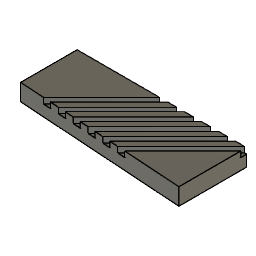
strip_cut (Autodesk Fusion 360 design; units mm, degrees)
Autodesk Fusion 360 part; units mm, degrees
sketch "Sketch1" plane through (0, 0, 0) normal (0, 0, 1) x (1, 0, 0)
  line L0 (0, 0) -> (30, -2)
  line L1 (30, -2) -> (30, 10)
  line L2 (30, 10) -> (0, 10)
  line L3 (0, 10) -> (0, 0)
extrude "Extrude1" add sketch "Sketch1" along normal blind 3
sketch "Sketch2" plane through (0, 0, 3) normal (0, 0, 1) x (1, 0, 0)
  line L0 (0, 10) -> (0, 0)
  line L1 (0, 0) -> (30, -2)
  line L2 (30, -2) -> (30, 10)
  line L3 (30, 10) -> (0, 10)
  line L4 (0, 10) -> (0, 0)
  line L5 (0, 0) -> (30, -2)
  line L6 (30, -2) -> (30, 10)
  line L7 (30, 10) -> (0, 10)
  line L8 (2.5251, -2.1011) -> (16.394, 11.7678)
  line L9 (16.394, 11.7678) -> (17.1011, 11.0607)
  line L10 (17.1011, 11.0607) -> (3.2322, -2.8082)
  line L11 (3.2322, -2.8082) -> (2.5251, -2.1011)
extrude "Extrude2" cut sketch "Sketch2" against normal blind 1 contours L3 L7 L8 L9 L10 | L1 L3 L5 L7 L8 L10 | L1 L5 L8 L10 L11
pattern_linear "R-Pattern1" count 6 spacing 3 along (1, 0, 0) count 3 spacing 0 along (1, 0, 0) of "Extrude2"
